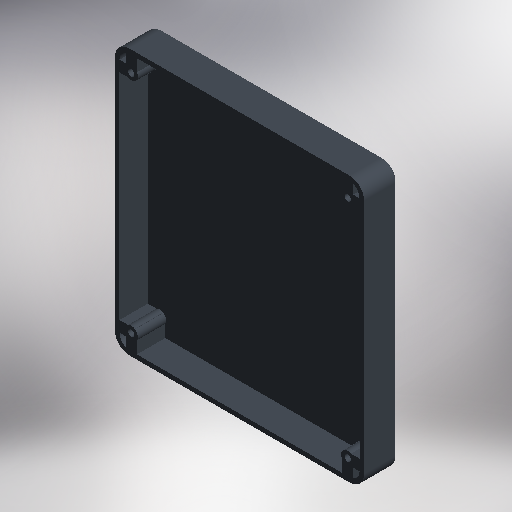
# Autodesk Inventor part: Enclosure_Base_Bottom
Saved by Autodesk Inventor 2027.1 (Build 311270010, 270A)
## iProperties
Part Number: Enclosure_Base_Bottom
Material: Generic
Document SubType Name: Modeling
Designer: austin
Appearance: Enclosure_Satin_Anthracite
Author: austin
Autodesk Inventor part; units mm, degrees
ref_plane "YZ Plane" through (0, 0, 0) normal (1, 0, 0) x (0, 1, 0)
sketch "Sketch1" plane through (0, 0, 0) normal (0, 0, 1) x (1, 0, 0)
  line L0 (-60, 0) -> (60, 0)
  arc A0 (60, 0) -> (68, 8) centre (60, 8) ccw
  line L1 (68, 8) -> (68, 137)
  arc A1 (68, 137) -> (60, 145) centre (60, 137) ccw
  line L2 (60, 145) -> (-60, 145)
  arc A2 (-60, 145) -> (-68, 137) centre (-60, 137) ccw
  line L3 (-68, 137) -> (-68, 8)
  arc A3 (-68, 8) -> (-60, 0) centre (-60, 8) ccw
  constraints: 8 end point, 8 point on circle, 4 centre point
extrude "Extrusion1" add sketch "Sketch1" along normal blind 18
ref_plane "Work Plane1" through (0, 0, 18) normal (0, 0, 1) x (1, 0, 0)
sketch "Sketch2" plane through (0, 0, 18) normal (0, 0, 1) x (1, 0, 0)
  line L0 (-60, 2.5) -> (60, 2.5)
  arc A0 (60, 2.5) -> (65.5, 8) centre (60, 8) ccw
  line L1 (65.5, 8) -> (65.5, 137)
  arc A1 (65.5, 137) -> (60, 142.5) centre (60, 137) ccw
  line L2 (60, 142.5) -> (-60, 142.5)
  arc A2 (-60, 142.5) -> (-65.5, 137) centre (-60, 137) ccw
  line L3 (-65.5, 137) -> (-65.5, 8)
  arc A3 (-65.5, 8) -> (-60, 2.5) centre (-60, 8) ccw
  constraints: 8 end point, 8 point on circle, 4 centre point
extrude "Extrusion2" cut sketch "Sketch2" against normal blind 15.5
sketch "Sketch3" plane through (0, 0, 0) normal (0, 0, 1) x (1, 0, 0)
  circle A0 centre (-52, 18) radius 6.25
  circle A1 centre (52, 18) radius 6.25
  circle A2 centre (-52, 127) radius 6.25
  circle A3 centre (52, 127) radius 6.25
  constraints: 4 centre point
extrude "Extrusion3" cut sketch "Sketch3" along normal blind 1.5
sketch "Sketch4" plane through (0, 0, 0) normal (0, 0, 1) x (1, 0, 0)
  circle A0 centre (-59, 11) radius 1.7
  circle A1 centre (59, 11) radius 1.7
  circle A2 centre (-59, 134) radius 1.7
  circle A3 centre (59, 134) radius 1.7
  constraints: 4 centre point
extrude "Extrusion4" cut sketch "Sketch4" along normal blind 3.5
ref_plane "Work Plane2" through (0, 0, 2.5) normal (0, 0, 1) x (1, 0, 0)
sketch "Sketch5" plane through (0, 0, 2.5) normal (0, 0, 1) x (1, 0, 0)
  circle A0 centre (-59, 11) radius 3.5
  circle A1 centre (59, 11) radius 3.5
  circle A2 centre (-59, 134) radius 3.5
  circle A3 centre (59, 134) radius 3.5
  constraints: 4 centre point
extrude "Extrusion5" add sketch "Sketch5" along normal blind 15.5
sketch "Sketch6" plane through (0, 0, 2.5) normal (0, 0, 1) x (1, 0, 0)
  line L0 (57, 131) -> (66.5, 131)
  line L1 (66.5, 131) -> (66.5, 137)
  line L2 (66.5, 137) -> (57, 137)
  line L3 (57, 137) -> (57, 131)
  line L4 (56, 133) -> (56, 143.5)
  line L5 (56, 143.5) -> (62, 143.5)
  line L6 (62, 143.5) -> (62, 133)
  line L7 (62, 133) -> (56, 133)
  line L8 (-66.5, 131) -> (-57, 131)
  line L9 (-57, 131) -> (-57, 137)
  line L10 (-57, 137) -> (-66.5, 137)
  line L11 (-66.5, 137) -> (-66.5, 131)
  line L12 (-62, 133) -> (-62, 143.5)
  line L13 (-62, 143.5) -> (-56, 143.5)
  line L14 (-56, 143.5) -> (-56, 133)
  line L15 (-56, 133) -> (-62, 133)
  line L16 (57, 8) -> (66.5, 8)
  line L17 (66.5, 8) -> (66.5, 14)
  line L18 (66.5, 14) -> (57, 14)
  line L19 (57, 14) -> (57, 8)
  line L20 (56, 1.5) -> (56, 12)
  line L21 (56, 12) -> (62, 12)
  line L22 (62, 12) -> (62, 1.5)
  line L23 (62, 1.5) -> (56, 1.5)
  line L24 (-66.5, 8) -> (-57, 8)
  line L25 (-57, 8) -> (-57, 14)
  line L26 (-57, 14) -> (-66.5, 14)
  line L27 (-66.5, 14) -> (-66.5, 8)
  line L28 (-62, 1.5) -> (-62, 12)
  line L29 (-62, 12) -> (-56, 12)
  line L30 (-56, 12) -> (-56, 1.5)
  line L31 (-56, 1.5) -> (-62, 1.5)
  constraints: 64 end point
extrude "Extrusion6" add sketch "Sketch6" along normal blind 15.5
sketch "Sketch7" plane through (0, 0, 18) normal (0, 0, 1) x (1, 0, 0)
  circle A0 centre (-59, 11) radius 1.7
  circle A1 centre (59, 11) radius 1.7
  circle A2 centre (-59, 134) radius 1.7
  circle A3 centre (59, 134) radius 1.7
  constraints: 4 centre point
extrude "Extrusion7" cut sketch "Sketch7" against normal blind 16
fillet "Fillet1" radius 1.5 16 edges at (-60.7, 134, 0) (-60.7, 11, 0) (57.3, 11, 0) (57.3, 134, 0) (-58.25, 127, 0) (-58.25, 18, 0) (45.75, 18, 0) (45.75, 127, 0) (-65.6569, 2.3431, 0) (-68, 72.5, 0) (-65.6569, 142.6569, 0) (0, 145, 0) (65.6569, 142.6569, 0) (68, 72.5, 0) (65.6569, 2.3431, 0) (0, 0, 0)
body "Solid1"
